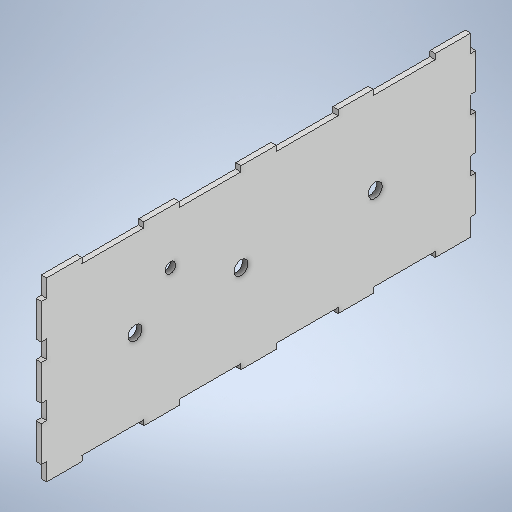
# Autodesk Inventor part: Lateral_derecho
Saved by Autodesk Inventor 2025.2 (Build 292293000, 293)
## iProperties
Created: 2025-05-16
Part Number: Lateral_derecho
Material: Generic
Document SubType Name: Modeling
Designer: laura
Density: 1 g/cm^3
Appearance: Default
ancho: 220.000 mm
largo: 310.000 mm
d_fila1: 40.000 mm
d_fila2: 10.000 mm
d_fila3: 66.000 mm
d_eje: 8.000 mm
alto: 100.000 mm
Author: laura
Autodesk Inventor part; units mm, degrees
ref_plane "YZ Plane" through (0, 0, 0) normal (1, 0, 0) x (0, 1, 0)
ref_plane "XZ Plane" through (0, 0, 0) normal (0, 1, 0) x (-1, 0, 0)
ref_plane "XY Plane" through (0, 0, 0) normal (0, 0, 1) x (1, 0, 0)
sketch "Sketch1" plane through (0, 0, 0) normal (1, 0, 0) x (0, 1, 0)
  line L0 (50, 120) -> (50, -120)
  line L1 (50, -120) -> (-50, -120)
  line L2 (-50, -120) -> (-50, 120)
  line L3 (-50, 120) -> (50, 120)
  line L4 (0, 120) -> (0, -120) construction
  circle A0 centre (-2, 70) radius 4
  circle A1 centre (0, -66) radius 4
  circle A2 centre (0, 10) radius 4
  line L5 (0, 70) -> (-2, 70) construction
  point P0 (0, 0)
  point P1 (0, 0)
  dimension "d0" = 240
  dimension "d1" = 100
  dimension "d3" = 10
  dimension "d5" = 8
  dimension "d8" = 2
  dimension "d33" = 76
  dimension "d34" = 60
  constraints: 12 end point, 4 coincident, 3 centre point, 3 midpoint, 3 point on line, 2 equal radius, 2 horizontal, 2 perpendicular, 1 vertical
  measures "d0" distance of L0.start L0.end
  measures "d1" distance of L0.end L1.end
  measures "d3" distance of point (0, 0) point (0, 10)
  measures "d5" diameter of A0
  measures "d8" distance of L5.start L5.end
  measures "d33" distance of point (0, -66) point (0, 10)
  measures "d34" vertical distance of A0.centre point (0, 10)
extrude "Extrusion1" add sketch "Sketch1" along normal blind 3
sketch "Sketch2" plane through (0, 0, 0) normal (-1, 0, 0) x (0, 0, 1)
  circle A0 centre (70, -2) radius 4 projected
  line L0 (120, -50) -> (-120, -50) projected
  line L1 (120, 50) -> (120, -50) projected
  line L2 (-120, 50) -> (120, 50) projected
  line L3 (-120, -50) -> (-120, 50) projected
  circle A1 centre (10, 0) radius 4 projected
  circle A2 centre (-66, 0) radius 4 projected
  circle A3 centre (70, -2) radius 4 projected
  circle A4 centre (50, 20) radius 3
  line L4 (50, -2) -> (50, 20) construction
  line L5 (10, 0) -> (10, -2) construction
  line L6 (10, -2) -> (50, -2) construction
  point P0 (0, 0)
  dimension "d9" = 6
  dimension "d11" = 22
  dimension "d35" = 40
  dimension "d36" = 2
  constraints: 6 end point, 2 vertical, 1 centre point, 1 coincident, 1 perpendicular
  measures "d9" diameter of A4
  measures "d11" distance of L4.start L4.end
  measures "d35" distance of L5.end L4.start
  measures "d36" distance of L5.start L5.end
extrude "Extrusion2" cut sketch "Sketch2" against normal through all contours A4
sketch "Sketch3" plane through (0, 0, 0) normal (-1, 0, 0) x (0, 0, 1)
  line L0 (-120, 50) -> (120, 50) projected
  line L1 (-100.01, 50) -> (-100.01, 47)
  line L2 (-100.01, 47) -> (-64.9975, 47)
  line L3 (-64.9975, 47) -> (-64.9975, 50)
  line L4 (-45.0075, 50) -> (-45.0075, 47)
  line L5 (-45.0075, 47) -> (-9.995, 47)
  line L6 (-9.995, 47) -> (-9.995, 50)
  line L7 (9.995, 50) -> (9.995, 47)
  line L8 (9.995, 47) -> (45.0075, 47)
  line L9 (45.0075, 47) -> (45.0075, 50)
  line L10 (64.9975, 50) -> (64.9975, 47)
  line L11 (64.9975, 47) -> (100.01, 47)
  line L12 (100.01, 47) -> (100.01, 50)
  line L13 (-120, -50) -> (-120, 50) projected
  line L14 (120, 50) -> (120, -50) projected
  line L15 (120, 40) -> (123, 40)
  line L16 (123, 40) -> (123, 20)
  line L17 (123, 20) -> (120, 20)
  line L18 (120, 10) -> (123, 10)
  line L19 (123, 10) -> (123, -10)
  line L20 (120, -20) -> (123, -20)
  line L21 (123, -20) -> (123, -40)
  line L22 (123, -40) -> (120, -40)
  line L23 (120, 50) -> (120, -50) projected
  line L24 (120, -50) -> (-120, -50) projected
  line L25 (123, -10) -> (120, -10)
  point P0 (0, 0)
  dimension "d15" = 19.99
  dimension "d16" = 19.99
  dimension "d17" = 19.99
  dimension "d18" = 19.99
  dimension "d19" = 19.99
  dimension "d20" = 3
  dimension "d23" = 10
  dimension "d24" = 10
  dimension "d28" = 10
  dimension "d29" = 10
  dimension "d30" = 3
  constraints: 42 end point, 15 point on line, 12 perpendicular, 6 collinear, 4 vertical, 2 parallel, 9 other
  measures "d15" distance between parallel lines of L1 L13
  measures "d16" distance between parallel lines of L4 L3
  measures "d17" distance between parallel lines of L7 L6
  measures "d18" distance between parallel lines of L10 L9
  measures "d19" distance between parallel lines of L14 L12
  measures "d24" distance between parallel lines of L18 L17
  measures "d28" distance between parallel lines of L24 L22
  measures "d29" distance between parallel lines of L20 L25
  measures "d30" distance between parallel lines of L14 L16
extrude "Extrusion3" cut sketch "Sketch3" against normal through all contours L0 L3 L2 L1 | L0 L6 L5 L4 | L0 L9 L8 L7 | L0 L12 L11 L10
extrude "Extrusion4" add sketch "Sketch3" against normal blind 3 contours L14 L20 L21 L22 | L14 L18 L19 L25 | L14 L15 L16 L17
mirror "Mirror1" about plane through (0, 0, 0) normal (0, 1, 0) of "Extrusion3"
mirror "Mirror2" about plane through (0, 0, 0) normal (0, 0, 1) of "Extrusion4"
equation "\"d1\" = alto"
equation "\"d3\" = d_fila2"
equation "\"d5\" = d_eje"
equation "\"d_eje\" = 8"
equation "\"alto\" = 100"
equation "\"d_fila2\" = 10"
body "Solid1"
